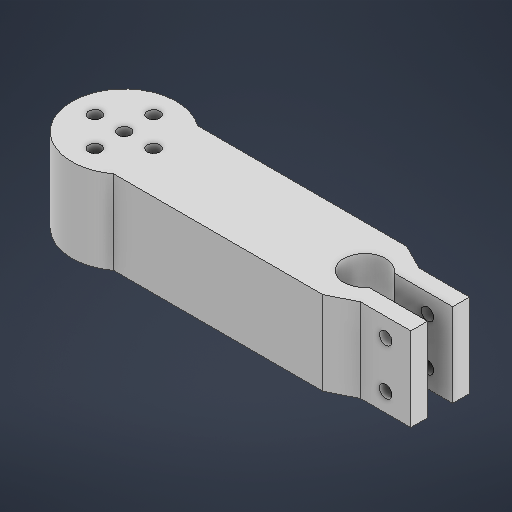
# Autodesk Inventor part: lien_servo_nageoire
Saved by Autodesk Inventor 2026.1 (Build 301233020, 233B)
## iProperties
Created: 2026-10-28
Part Number: lien_servo_nageoire
Material: Generic
Document SubType Name: Modeling
Designer: matar
Density: 1 g/cm^3
Appearance: Default
Author: matar
Autodesk Inventor part; units mm, degrees
ref_plane "YZ Plane" through (0, 0, 0) normal (1, 0, 0) x (0, 1, 0)
ref_plane "XZ Plane" through (0, 0, 0) normal (0, 1, 0) x (-1, 0, 0)
ref_plane "XY Plane" through (0, 0, 0) normal (0, 0, 1) x (1, 0, 0)
sketch "Sketch2" plane through (0, 0, 0) normal (0, 1, 0) x (-1, 0, 0)
  line L0 (0, 0) -> (50, 0)
  line L1 (50, -20) -> (0, -20)
  arc A0 (50, -20) -> (50, 0) centre (57.5, -10) ccw
  line L2 (0, -20) -> (-6, -17)
  line L3 (0, 0) -> (-6, -3)
  line L4 (-6, -3) -> (-18, -3)
  line L5 (-18, -3) -> (-18, -7)
  line L6 (-18, -7) -> (-4, -7)
  line L7 (-6, -17) -> (-18, -17)
  line L8 (-18, -17) -> (-18, -13)
  line L9 (-18, -13) -> (-4, -13)
  arc A1 (-4, -13) -> (-4, -7) centre (0, -10) ccw
  point P0 (70, -10)
  dimension "d1" = 20
  dimension "d4" = 12.5
  dimension "d6" = 50
  dimension "d7" = 50
  dimension "d8" = 4
  dimension "d9" = 4
  dimension "d10" = 12
  dimension "d11" = 12
  dimension "d12" = 14
  dimension "d13" = 14
  dimension "d14" = 5
  constraints: 20 end point, 5 point on circle, 4 perpendicular, 3 horizontal, 2 centre point, 1 parallel
  measures "d1" distance of L1.end L0.start
  measures "d4" radius of A0
  measures "d6" distance of L1.start L1.end
  measures "d7" distance of L0.start L0.end
  measures "d8" distance of L4.end L5.end
  measures "d9" distance of L7.end L8.end
  measures "d10" distance of L3.end L4.end
  measures "d11" distance of L2.end L7.end
  measures "d12" distance of L5.end L6.end
  measures "d13" distance of L8.end L9.end
  measures "d14" radius of A1
extrude "Extrusion1" add sketch "Sketch2" along normal blind 20
sketch "Sketch3" plane through (6, 0, -3) normal (0, 0, 1) x (1, 0, 0)
  circle A0 centre (6, 15.5) radius 1.5
  circle A1 centre (6, 4.5) radius 1.5
  line L0 (0, 20) -> (12, 20) projected
  line L1 (0, 0) -> (12, 0) projected
  line L2 (12, 0) -> (12, 20) projected
  point P0 (-6, 0)
  point P1 (6, 20)
  point P2 (6, 0)
  dimension "d17" = 3
  dimension "d18" = 3
  dimension "d19" = 4.5
  dimension "d20" = 4.5
  dimension "d21" = 6
  dimension "d22" = 6
  constraints: 2 centre point, 2 midpoint
  measures "d17" diameter of A0
  measures "d18" diameter of A1
  measures "d19" distance of point (6, 20) A0.centre
  measures "d20" distance of point (6, 0) A1.centre
  measures "d21" distance from line of L2 A0.centre
  measures "d22" distance from line of L2 A1.centre
extrude "Extrusion2" cut sketch "Sketch3" against normal blind 15
sketch "Sketch4" plane through (0, 20, 0) normal (0, 1, 0) x (1, 0, 0)
  circle A0 centre (-57.5, 10) radius 1.5
  arc A1 (-50, 20) -> (-50, 0) centre (-57.5, 10) ccw projected
  circle A2 centre (-57.5, 17) radius 1.5
  circle A3 centre (-50.5, 10) radius 1.5
  circle A4 centre (-57.5, 3) radius 1.5
  circle A5 centre (-64.5, 10) radius 1.5
  point P0 (0, 0)
  point P1 (-70, 10)
  dimension "d25" = 3
  dimension "d26" = 0
  dimension "d27" = 0
  dimension "d29" = 3
  dimension "d30" = 3
  dimension "d31" = 3
  dimension "d32" = 3
  dimension "d33" = 7
  dimension "d34" = 7
  dimension "d35" = 7
  dimension "d36" = 7
  constraints: 5 centre point, 1 point on circle
  measures "d25" diameter of A0
  measures "d26" vertical distance of point (-70, 10) A0.centre
  measures "d27" distance of A1.centre A0.centre
  measures "d29" diameter of A2
  measures "d30" diameter of A3
  measures "d31" diameter of A4
  measures "d32" diameter of A5
  measures "d33" distance of A3.centre A0.centre
  measures "d34" distance of A5.centre A0.centre
  measures "d35" distance of A2.centre A0.centre
  measures "d36" distance of A4.centre A0.centre
extrude "Extrusion3" cut sketch "Sketch4" against normal through all
sketch "Sketch5" plane through (0, 0, 0) normal (0, -1, 0) x (1, 0, 0)
  circle A0 centre (-57.5, -10) radius 10.25
  circle A1 centre (-57.5, -10) radius 1.5 projected
  point P0 (0, 0)
  dimension "d39" = 20.5
  dimension "d40" = 0
  dimension "d41" = 0
  constraints: 1 centre point
  measures "d39" diameter of A0
  measures "d40" distance of A1.centre A0.centre
  measures "d41" distance of A1.centre A0.centre
extrude "Extrusion4" cut sketch "Sketch5" against normal blind 6
sketch "Sketch6" plane through (-57.5, 6, -10) normal (0, -1, 0) x (1, 0, 0)
  circle A0 centre (0, 0) radius 4.1
  point P0 (57.5, 10)
  dimension "d44" = 8.2
  constraints: 1 centre point
  measures "d44" diameter of A0
extrude "Extrusion5" cut sketch "Sketch6" against normal blind 2
body "Solid1"
